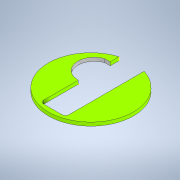
# Autodesk Inventor part: inglobare_baterie_cu_decupaj_buton
Saved by Autodesk Inventor 2022.6 (Build 266554000, 554)
## iProperties
Created: 2025-06-10
Part Number: inglobare_baterie_cu_decupaj_buton
Material: Generic
Document SubType Name: Modeling
Designer: Dragos Macovei
Density: 1 g/cm^3
Appearance: Default
Author: Dragos Macovei
Autodesk Inventor part; units mm, degrees
ref_plane "YZ Plane" through (0, 0, 0) normal (1, 0, 0) x (0, 1, 0)
ref_plane "XZ Plane" through (0, 0, 0) normal (0, 1, 0) x (-1, 0, 0)
ref_plane "XY Plane" through (0, 0, 0) normal (0, 0, 1) x (1, 0, 0)
sketch "Sketch1" plane through (0, 0, 0) normal (0, 1, 0) x (-1, 0, 0)
  arc A0 (21.5, -69.2387) -> (-21.5, -69.2387) centre (0, 0) ccw
  line L0 (21.5, 65) -> (-21.5, 65)
  line L1 (-21.5, 65) -> (-21.5, -65)
  line L2 (-21.5, -65) -> (21.5, -65)
  line L3 (21.5, -65) -> (21.5, 65)
  line L4 (21.5, -65) -> (21.5, -69.2387)
  line L5 (-21.5, -65) -> (-21.5, -69.2387)
  dimension "d0" = 145
  dimension "d1" = 43
  dimension "d2" = 130
  dimension "d3" = 65
  dimension "d4" = 21.5
  constraints: 12 end point, 2 parallel, 2 point on circle, 2 vertical, 1 centre point, 1 coincident, 1 horizontal, 1 perpendicular
  measures "d0" diameter of A0
  measures "d1" distance of L2.end L1.end
  measures "d2" distance of L1.end L0.end
  measures "d3" distance from line of L2 point (0, 0)
  measures "d4" distance from line of point (0, 0) L3
extrude "Extrusion1" add sketch "Sketch1" along normal blind 6 contours L4 L3 L0 L1 L5 A0
fillet "Fillet1" radius 6 2 edges at (-21.5, 3, 65) (21.5, 3, 65)
sketch "Sketch2" plane through (-21.5, 0, -69.2387) normal (1, 0, 0) x (0, 0, -1)
  line L0 (0, 0) -> (0, 0) projected
  line L1 (0, 0) -> (0, 6) projected
  line L2 (0, 6) -> (0, 6) projected
  line L3 (0, 0) -> (0, 6) projected
  point P0 (-69.2387, 0)
sketch "Sketch3" plane through (-21.5, 0, -69.2387) normal (1, 0, 0) x (0, 0, -1)
  line L0 (0, 0) -> (0, 0) projected
  line L1 (0, 0) -> (0, 6) projected
  line L2 (0, 6) -> (0, 6) projected
  line L3 (0, 0) -> (0, 6) projected
  line L4 (0, 6) -> (-141.7387, 6) projected
  line L5 (0, 0) -> (-141.7387, 0) projected
  line L6 (-25.7, 6) -> (-15, 6)
  line L7 (-15, 6) -> (-15, 0)
  line L8 (-15, 0) -> (-25.7, 0)
  line L9 (-25.7, 0) -> (-25.7, 6)
  point P0 (-69.2387, 0)
  point P1 (-25.7, 0)
  point P2 (-15, 6)
  point P3 (0, 3)
  point P4 (-15, 3)
  dimension "d8" = 10.7
  dimension "d11" = 15
  constraints: 8 end point, 2 midpoint, 2 parallel, 2 point on line, 1 horizontal, 1 perpendicular
  measures "d8" distance of L7.end L8.end
  measures "d11" distance of point (0, 3) point (-15, 3)
extrude "Extrusion2" cut sketch "Sketch3" against normal blind 9 contours L5 L9 L4 L7
sketch "Sketch4" plane through (0, 6, 0) normal (0, 1, 0) x (1, 0, 0)
  line L0 (-30.5, 54.2387) -> (-30.5, 43.5387) projected
  line L1 (-21.5, -59) -> (-21.5, 43.5387) projected
  arc A0 (-30.5, 54.2387) -> (-21.5, -0.0504) centre (-22.1608, 27.7306) ccw
  line L2 (-21.5, 43.5387) -> (-30.5, 43.5387) projected
  arc A1 (-30.5, 43.5387) -> (-21.5, 10.6496) centre (-22.0461, 28.1761) ccw
  point P0 (0, 0)
  dimension "d12" = 10.7
  constraints: 4 point on circle, 2 centre point, 1 point on line
  measures "d12" distance of A0.end A1.end
extrude "Extrusion3" cut sketch "Sketch4" against normal blind 9
equation "\"d3\" = 0.5 * d2"
body "Solid1"
